Autodesk Fusion 360 part; units mm, degrees
(part 8 of 18)
  line L5414 (35.57, -188.553) -> (35.8785, -188.046)
  line L5415 (35.8585, -188.27) -> (35.5441, -188.763)
  line L5416 (63.4315, -180.974) -> (63.6222, -180.422)
  line L5417 (36.3887, -187.23) -> (36.1404, -187.759)
  line L5418 (81.0274, -184.988) -> (80.9224, -185.562)
  line L5419 (30.5713, -174.951) -> (31.1275, -175.13)
  line L5420 (25.9488, -174.854) -> (26.5208, -174.735)
  line L5421 (22.539, -190.687) -> (23.0175, -191.039)
  line L5422 (23.2676, -175.984) -> (23.7724, -175.689)
  line L5423 (32.954, -176.14) -> (32.4456, -175.833)
  line L5424 (100.022, -190.347) -> (100.453, -189.938)
  line L5425 (90.138, -191.798) -> (89.6204, -191.527)
  line L5426 (68.138, -191.798) -> (67.6204, -191.527)
  line L5427 (33.5358, -190.868) -> (33.0587, -191.205)
  line L5428 (25.6987, -192.283) -> (26.2761, -192.422)
  line L5429 (36.4559, -180.231) -> (36.6591, -180.778)
  line L5430 (102.972, -184.679) -> (103.021, -184.087)
  line L5431 (81.1268, -183.65) -> (81.1251, -183.824)
  line L5432 (28.2663, -174.602) -> (28.8498, -174.633)
  line L5433 (64.3113, -188.298) -> (64.0276, -187.787)
  line L5434 (36.6591, -180.778) -> (36.8266, -181.338)
  line L5435 (25.3856, -175.009) -> (25.9488, -174.854)
  line L5436 (90.9847, -175.246) -> (90.4345, -175.469)
  line L5437 (34.8557, -189.501) -> (35.2286, -189.039)
  line L5438 (63.9741, -187.463) -> (64.2446, -187.991)
  line L5439 (87.5489, -177.52) -> (87.157, -177.966)
  line L5440 (67.5183, -191.358) -> (68.0392, -191.643)
  line L5441 (64.1085, -179.36) -> (64.402, -178.854)
  line L5442 (63.1742, -184.617) -> (63.2578, -185.205)
  line L5443 (85.5618, -186.716) -> (85.3817, -186.16)
  line L5444 (28.0926, -192.7) -> (27.5085, -192.682)
  line L5445 (85.541, -186.358) -> (85.7392, -186.917)
  line L5446 (68.672, -192.035) -> (68.138, -191.798)
  line L5447 (28.6391, -192.587) -> (29.2302, -192.53)
  line L5448 (65.3513, -189.706) -> (64.9746, -189.259)
  line L5449 (33.9903, -190.501) -> (33.5358, -190.868)
  line L5450 (21.157, -177.966) -> (20.7955, -178.437)
  line L5451 (70.9269, -192.627) -> (70.35, -192.534)
  line L5452 (19.3443, -181.666) -> (19.232, -182.249)
  line L5453 (100.856, -189.501) -> (101.229, -189.039)
  line L5454 (22.643, -190.887) -> (22.1873, -190.521)
  line L5455 (34.0223, -190.347) -> (34.453, -189.938)
  line L5456 (93.8893, -174.697) -> (93.2963, -174.729)
  line L5457 (68.5778, -191.893) -> (69.1318, -192.107)
  line L5458 (65.6569, -189.893) -> (66.0847, -190.305)
  line L5459 (20.17, -179.446) -> (19.9088, -179.979)
  line L5460 (74.5713, -174.951) -> (75.1275, -175.13)
  line L5461 (24.672, -192.035) -> (24.138, -191.798)
  line L5462 (24.8336, -175.201) -> (25.3856, -175.009)
  line L5463 (19.7392, -186.917) -> (19.9741, -187.463)
  line L5464 (20.9746, -189.259) -> (20.6274, -188.789)
  line L5465 (65.7561, -190.127) -> (65.3513, -189.706)
  line L5466 (85.495, -181.092) -> (85.3443, -181.666)
  line L5467 (85.7774, -187.259) -> (85.5618, -186.716)
  line L5468 (35.6409, -178.681) -> (35.9457, -179.18)
  line L5469 (90.672, -192.035) -> (90.138, -191.798)
  line L5470 (101.133, -178.137) -> (100.753, -177.681)
  line L5471 (34.7525, -177.681) -> (34.3423, -177.252)
  line L5472 (19.9088, -179.979) -> (19.6834, -180.529)
  line L5473 (67.7724, -175.689) -> (68.2951, -175.428)
  line L5474 (25.7803, -192.404) -> (25.2202, -192.237)
  line L5475 (91.1318, -192.107) -> (91.6987, -192.283)
  line L5476 (36.8847, -185.267) -> (36.9725, -184.679)
  line L5477 (94.483, -174.704) -> (93.8893, -174.697)
  line L5478 (30.3945, -192.3) -> (30.9627, -192.127)
  line L5479 (20.0276, -187.787) -> (19.7774, -187.259)
  line L5480 (29.4301, -174.702) -> (30.0047, -174.808)
  line L5481 (24.5778, -191.893) -> (25.1318, -192.107)
  line L5482 (24.4345, -175.469) -> (23.9003, -175.729)
  line L5483 (34.1207, -176.914) -> (34.5428, -177.318)
  line L5484 (90.4345, -175.469) -> (89.9003, -175.729)
  line L5485 (73.2302, -192.53) -> (73.8162, -192.434)
  line L5486 (86.5495, -188.501) -> (86.8876, -188.989)
  line L5487 (63.7774, -187.259) -> (63.5618, -186.716)
  line L5488 (26.8615, -192.522) -> (27.4521, -192.583)
  line L5489 (36.1404, -187.759) -> (35.8585, -188.27)
  line L5490 (29.8162, -192.434) -> (30.3945, -192.3)
  line L5491 (37.1268, -183.65) -> (37.1251, -183.824)
  line L5492 (90.5778, -191.893) -> (91.1318, -192.107)
  line L5493 (63.1309, -185.019) -> (63.0612, -184.439)
  line L5494 (26.1233, -174.911) -> (25.5484, -175.059)
  line L5495 (20.6274, -188.789) -> (20.3113, -188.298)
  line L5496 (19.541, -186.358) -> (19.7392, -186.917)
  line L5497 (63.0332, -183.431) -> (63.0347, -183.271)
  line L5498 (65.2572, -189.454) -> (65.6569, -189.893)
  line L5499 (31.3734, -175.324) -> (30.8143, -175.124)
  line L5500 (29.075, -174.751) -> (28.483, -174.704)
  line L5501 (90.0392, -191.643) -> (90.5778, -191.893)
  line L5502 (92.9269, -192.627) -> (92.35, -192.534)
  line L5503 (85.0347, -183.271) -> (85.078, -182.688)
  line L5504 (50.8498, -174.633) -> (51.4301, -174.702)
  line L5505 (51.4301, -174.702) -> (52.0047, -174.808)
  line L5506 (52.0047, -174.808) -> (52.5713, -174.951)
  line L5507 (52.5713, -174.951) -> (53.1275, -175.13)
  line L5508 (53.1275, -175.13) -> (53.671, -175.344)
  line L5509 (53.671, -175.344) -> (54.1995, -175.594)
  line L5510 (54.1995, -175.594) -> (54.7108, -175.876)
  line L5511 (54.7108, -175.876) -> (55.2028, -176.192)
  line L5512 (55.2028, -176.192) -> (55.6734, -176.538)
  line L5513 (55.6734, -176.538) -> (56.1207, -176.914)
  line L5514 (56.1207, -176.914) -> (56.5428, -177.318)
  line L5515 (56.5428, -177.318) -> (56.9379, -177.749)
  line L5516 (56.9379, -177.749) -> (57.3045, -178.204)
  line L5517 (57.3045, -178.204) -> (57.6409, -178.681)
  line L5518 (57.6409, -178.681) -> (57.9457, -179.18)
  line L5519 (57.9457, -179.18) -> (58.2178, -179.697)
  line L5520 (58.2178, -179.697) -> (58.4559, -180.231)
  line L5521 (58.4559, -180.231) -> (58.6591, -180.778)
  line L5522 (58.6591, -180.778) -> (58.8266, -181.338)
  line L5523 (58.8266, -181.338) -> (58.9575, -181.908)
  line L5524 (58.9575, -181.908) -> (59.0514, -182.484)
  line L5525 (59.0514, -182.484) -> (59.1079, -183.066)
  line L5526 (59.1079, -183.066) -> (59.1268, -183.65)
  line L5527 (59.1268, -183.65) -> (59.1251, -183.824)
  line L5528 (59.1251, -183.824) -> (59.0951, -184.407)
  line L5529 (59.0951, -184.407) -> (59.0274, -184.988)
  line L5530 (59.0274, -184.988) -> (58.9224, -185.562)
  line L5531 (58.9224, -185.562) -> (58.7806, -186.129)
  line L5532 (58.7806, -186.129) -> (58.6024, -186.686)
  line L5533 (58.6024, -186.686) -> (58.3887, -187.23)
  line L5534 (58.3887, -187.23) -> (58.1404, -187.759)
  line L5535 (58.1404, -187.759) -> (57.8585, -188.27)
  line L5536 (57.8585, -188.27) -> (57.5441, -188.763)
  line L5537 (57.5441, -188.763) -> (57.1986, -189.234)
  line L5538 (57.1986, -189.234) -> (56.8234, -189.682)
  line L5539 (56.8234, -189.682) -> (56.42, -190.105)
  line L5540 (56.42, -190.105) -> (55.9903, -190.501)
  line L5541 (55.9903, -190.501) -> (55.5358, -190.868)
  line L5542 (55.5358, -190.868) -> (55.0587, -191.205)
  line L5543 (55.0587, -191.205) -> (54.5607, -191.511)
  line L5544 (54.5607, -191.511) -> (54.0441, -191.784)
  line L5545 (54.0441, -191.784) -> (53.5109, -192.023)
  line L5546 (53.5109, -192.023) -> (52.9634, -192.227)
  line L5547 (52.9634, -192.227) -> (52.4039, -192.396)
  line L5548 (52.4039, -192.396) -> (51.8346, -192.528)
  line L5549 (51.8346, -192.528) -> (51.2581, -192.623)
  line L5550 (51.2581, -192.623) -> (50.6766, -192.68)
  line L5551 (50.6766, -192.68) -> (50.0926, -192.7)
  line L5552 (50.0926, -192.7) -> (49.5085, -192.682)
  line L5553 (49.5085, -192.682) -> (48.9269, -192.627)
  line L5554 (48.9269, -192.627) -> (48.35, -192.534)
  line L5555 (48.35, -192.534) -> (47.7803, -192.404)
  line L5556 (47.7803, -192.404) -> (47.2202, -192.237)
  line L5557 (47.2202, -192.237) -> (46.672, -192.035)
  line L5558 (46.672, -192.035) -> (46.138, -191.798)
  line L5559 (46.138, -191.798) -> (45.6204, -191.527)
  line L5560 (45.6204, -191.527) -> (45.1214, -191.223)
  line L5561 (45.1214, -191.223) -> (44.643, -190.887)
  line L5562 (44.643, -190.887) -> (44.1873, -190.521)
  line L5563 (44.1873, -190.521) -> (43.7561, -190.127)
  line L5564 (43.7561, -190.127) -> (43.3513, -189.706)
  line L5565 (43.3513, -189.706) -> (42.9746, -189.259)
  line L5566 (42.9746, -189.259) -> (42.6274, -188.789)
  line L5567 (42.6274, -188.789) -> (42.3113, -188.298)
  line L5568 (42.3113, -188.298) -> (42.0276, -187.787)
  line L5569 (42.0276, -187.787) -> (41.7774, -187.259)
  line L5570 (41.7774, -187.259) -> (41.5618, -186.716)
  line L5571 (41.5618, -186.716) -> (41.3817, -186.16)
  line L5572 (41.3817, -186.16) -> (41.2379, -185.593)
  line L5573 (41.2379, -185.593) -> (41.1309, -185.019)
  line L5574 (41.1309, -185.019) -> (41.0612, -184.439)
  line L5575 (41.0612, -184.439) -> (41.0291, -183.855)
  line L5576 (41.0291, -183.855) -> (41.0332, -183.431)
  line L5577 (41.0332, -183.431) -> (41.0347, -183.271)
  line L5578 (41.0347, -183.271) -> (41.078, -182.688)
  line L5579 (41.1742, -184.617) -> (41.2578, -185.205)
  line L5580 (41.2578, -185.205) -> (41.3803, -185.786)
  line L5581 (41.3803, -185.786) -> (41.541, -186.358)
  line L5582 (41.541, -186.358) -> (41.7392, -186.917)
  line L5583 (41.7392, -186.917) -> (41.9741, -187.463)
  line L5584 (41.9741, -187.463) -> (42.2446, -187.991)
  line L5585 (42.2446, -187.991) -> (42.5495, -188.501)
  line L5586 (42.5495, -188.501) -> (42.8876, -188.989)
  line L5587 (42.8876, -188.989) -> (43.2572, -189.454)
  line L5588 (43.2572, -189.454) -> (43.6569, -189.893)
  line L5589 (43.6569, -189.893) -> (44.0847, -190.305)
  line L5590 (44.0847, -190.305) -> (44.539, -190.687)
  line L5591 (44.539, -190.687) -> (45.0175, -191.039)
  line L5592 (45.0175, -191.039) -> (45.5183, -191.358)
  line L5593 (45.5183, -191.358) -> (46.0392, -191.643)
  line L5594 (46.0392, -191.643) -> (46.5778, -191.893)
  line L5595 (46.5778, -191.893) -> (47.1318, -192.107)
  line L5596 (47.1318, -192.107) -> (47.6987, -192.283)
  line L5597 (47.6987, -192.283) -> (48.2761, -192.422)
  line L5598 (48.2761, -192.422) -> (48.8615, -192.522)
  line L5599 (48.8615, -192.522) -> (49.4521, -192.583)
  line L5600 (49.4521, -192.583) -> (50.0455, -192.605)
  line L5601 (50.0455, -192.605) -> (50.6391, -192.587)
  line L5602 (50.6391, -192.587) -> (51.2302, -192.53)
  line L5603 (51.2302, -192.53) -> (51.8162, -192.434)
  line L5604 (51.8162, -192.434) -> (52.3945, -192.3)
  line L5605 (52.3945, -192.3) -> (52.9627, -192.127)
  line L5606 (52.9627, -192.127) -> (53.5182, -191.917)
  line L5607 (53.5182, -191.917) -> (54.0585, -191.671)
  line L5608 (54.0585, -191.671) -> (54.5813, -191.39)
  line L5609 (54.5813, -191.39) -> (55.0844, -191.074)
  line L5610 (55.0844, -191.074) -> (55.5654, -190.726)
  line L5611 (55.5654, -190.726) -> (56.0223, -190.347)
  line L5612 (56.0223, -190.347) -> (56.453, -189.938)
  line L5613 (56.453, -189.938) -> (56.8557, -189.501)
  line L5614 (56.8557, -189.501) -> (57.2286, -189.039)
  line L5615 (57.2286, -189.039) -> (57.57, -188.553)
  line L5616 (57.57, -188.553) -> (57.8785, -188.046)
  line L5617 (57.8785, -188.046) -> (58.1527, -187.519)
  line L5618 (58.1527, -187.519) -> (58.3914, -186.976)
  line L5619 (58.3914, -186.976) -> (58.5935, -186.417)
  line L5620 (58.5935, -186.417) -> (58.7582, -185.847)
  line L5621 (58.7582, -185.847) -> (58.8847, -185.267)
  line L5622 (58.8847, -185.267) -> (58.9725, -184.679)
  line L5623 (58.9725, -184.679) -> (59.0211, -184.087)
  line L5624 (59.0211, -184.087) -> (59.0318, -183.65)
  line L5625 (59.0318, -183.65) -> (59.0121, -183.057)
  line L5626 (59.0121, -183.057) -> (58.9531, -182.466)
  line L5627 (58.9531, -182.466) -> (58.8551, -181.88)
  line L5628 (58.8551, -181.88) -> (58.7185, -181.302)
  line L5629 (58.7185, -181.302) -> (58.5439, -180.735)
  line L5630 (58.5439, -180.735) -> (58.3321, -180.18)
  line L5631 (58.3321, -180.18) -> (58.084, -179.64)
  line L5632 (58.084, -179.64) -> (57.8006, -179.118)
  line L5633 (57.8006, -179.118) -> (57.4833, -178.617)
  line L5634 (57.4833, -178.617) -> (57.1334, -178.137)
  line L5635 (57.1334, -178.137) -> (56.7525, -177.681)
  line L5636 (56.7525, -177.681) -> (56.3423, -177.252)
  line L5637 (56.3423, -177.252) -> (55.9045, -176.851)
  line L5638 (55.9045, -176.851) -> (55.4411, -176.479)
  line L5639 (55.4411, -176.479) -> (54.954, -176.14)
  line L5640 (54.954, -176.14) -> (54.4456, -175.833)
  line L5641 (54.4456, -175.833) -> (53.9179, -175.561)
  line L5642 (53.9179, -175.561) -> (53.3734, -175.324)
  line L5643 (53.3734, -175.324) -> (52.8143, -175.124)
  line L5644 (52.8143, -175.124) -> (52.2432, -174.961)
  line L5645 (52.2432, -174.961) -> (51.6626, -174.837)
  line L5646 (51.6626, -174.837) -> (51.075, -174.751)
  line L5647 (51.075, -174.751) -> (50.483, -174.704)
  line L5648 (50.483, -174.704) -> (49.8893, -174.697)
  line L5649 (49.8893, -174.697) -> (49.2963, -174.729)
  line L5650 (49.2963, -174.729) -> (48.7068, -174.8)
  line L5651 (48.7068, -174.8) -> (48.1233, -174.911)
  line L5652 (48.1233, -174.911) -> (47.5484, -175.059)
  line L5653 (47.5484, -175.059) -> (46.9847, -175.246)
  line L5654 (46.9847, -175.246) -> (46.4345, -175.469)
  line L5655 (46.4345, -175.469) -> (45.9003, -175.729)
  line L5656 (45.9003, -175.729) -> (45.3845, -176.023)
  line L5657 (45.3845, -176.023) -> (44.8893, -176.351)
  line L5658 (44.8893, -176.351) -> (44.417, -176.71)
  line L5659 (44.417, -176.71) -> (43.9695, -177.101)
  line L5660 (43.9695, -177.101) -> (43.5489, -177.52)
  line L5661 (43.5489, -177.52) -> (43.157, -177.966)
  line L5662 (43.157, -177.966) -> (42.7955, -178.437)
  line L5663 (42.7955, -178.437) -> (42.466, -178.931)
  line L5664 (42.466, -178.931) -> (42.17, -179.446)
  line L5665 (42.17, -179.446) -> (41.9088, -179.979)
  line L5666 (41.9088, -179.979) -> (41.6834, -180.529)
  line L5667 (41.6834, -180.529) -> (41.495, -181.092)
  line L5668 (41.495, -181.092) -> (41.3443, -181.666)
  line L5669 (41.3443, -181.666) -> (41.2321, -182.249)
  line L5670 (41.2321, -182.249) -> (41.1587, -182.838)
  line L5671 (41.1587, -182.838) -> (41.1245, -183.431)
  line L5672 (41.1245, -183.431) -> (41.1297, -184.025)
  line L5673 (41.1297, -184.025) -> (41.1742, -184.617)
  line L5674 (129.078, -158.988) -> (129.159, -158.41)
  line L5675 (129.159, -158.41) -> (129.277, -157.837)
  line L5676 (129.277, -157.837) -> (129.432, -157.274)
  line L5677 (129.432, -157.274) -> (129.622, -156.722)
  line L5678 (129.622, -156.722) -> (129.848, -156.183)
  line L5679 (129.848, -156.183) -> (130.108, -155.66)
  line L5680 (130.108, -155.66) -> (130.402, -155.154)
  line L5681 (130.402, -155.154) -> (130.727, -154.669)
  line L5682 (130.727, -154.669) -> (131.084, -154.206)
  line L5683 (131.084, -154.206) -> (131.469, -153.766)
  line L5684 (131.469, -153.766) -> (131.882, -153.353)
  line L5685 (131.882, -153.353) -> (132.32, -152.967)
  line L5686 (132.32, -152.967) -> (132.783, -152.61)
  line L5687 (132.783, -152.61) -> (133.268, -152.284)
  line L5688 (133.268, -152.284) -> (133.772, -151.989)
  line L5689 (133.772, -151.989) -> (134.295, -151.728)
  line L5690 (134.295, -151.728) -> (134.834, -151.501)
  line L5691 (134.834, -151.501) -> (135.386, -151.309)
  line L5692 (135.386, -151.309) -> (135.949, -151.154)
  line L5693 (135.949, -151.154) -> (136.521, -151.035)
  line L5694 (136.521, -151.035) -> (137.099, -150.953)
  line L5695 (137.099, -150.953) -> (137.682, -150.909)
  line L5696 (137.682, -150.909) -> (138.266, -150.902)
  line L5697 (138.266, -150.902) -> (138.85, -150.933)
  line L5698 (138.85, -150.933) -> (139.43, -151.002)
  line L5699 (139.43, -151.002) -> (140.005, -151.108)
  line L5700 (140.005, -151.108) -> (140.571, -151.251)
  line L5701 (140.571, -151.251) -> (141.128, -151.43)
  line L5702 (141.128, -151.43) -> (141.671, -151.644)
  line L5703 (141.671, -151.644) -> (142.199, -151.894)
  line L5704 (142.199, -151.894) -> (142.711, -152.176)
  line L5705 (142.711, -152.176) -> (143.203, -152.492)
  line L5706 (143.203, -152.492) -> (143.673, -152.838)
  line L5707 (143.673, -152.838) -> (144.121, -153.214)
  line L5708 (144.121, -153.214) -> (144.543, -153.618)
  line L5709 (144.543, -153.618) -> (144.938, -154.049)
  line L5710 (144.938, -154.049) -> (145.304, -154.504)
  line L5711 (145.304, -154.504) -> (145.641, -154.981)
  line L5712 (145.641, -154.981) -> (145.946, -155.48)
  line L5713 (145.946, -155.48) -> (146.218, -155.997)
  line L5714 (146.218, -155.997) -> (146.456, -156.531)
  line L5715 (146.456, -156.531) -> (146.659, -157.078)
  line L5716 (146.659, -157.078) -> (146.827, -157.638)
  line L5717 (146.827, -157.638) -> (146.957, -158.208)
  line L5718 (146.957, -158.208) -> (147.051, -158.784)
  line L5719 (147.051, -158.784) -> (147.108, -159.366)
  line L5720 (147.108, -159.366) -> (147.127, -159.95)
  line L5721 (147.127, -159.95) -> (147.125, -160.124)
  line L5722 (147.125, -160.124) -> (147.095, -160.707)
  line L5723 (147.095, -160.707) -> (147.027, -161.288)
  line L5724 (147.027, -161.288) -> (146.922, -161.862)
  line L5725 (146.922, -161.862) -> (146.781, -162.429)
  line L5726 (146.781, -162.429) -> (146.602, -162.986)
  line L5727 (146.602, -162.986) -> (146.389, -163.53)
  line L5728 (146.389, -163.53) -> (146.14, -164.059)
  line L5729 (146.14, -164.059) -> (145.858, -164.57)
  line L5730 (145.858, -164.57) -> (145.544, -165.063)
  line L5731 (145.544, -165.063) -> (145.199, -165.534)
  line L5732 (145.199, -165.534) -> (144.823, -165.982)
  line L5733 (144.823, -165.982) -> (144.42, -166.405)
  line L5734 (144.42, -166.405) -> (143.99, -166.801)
  line L5735 (143.99, -166.801) -> (143.536, -167.168)
  line L5736 (143.536, -167.168) -> (143.059, -167.505)
  line L5737 (143.059, -167.505) -> (142.561, -167.811)
  line L5738 (142.561, -167.811) -> (142.044, -168.084)
  line L5739 (142.044, -168.084) -> (141.511, -168.323)
  line L5740 (141.511, -168.323) -> (140.963, -168.527)
  line L5741 (140.963, -168.527) -> (140.404, -168.696)
  line L5742 (140.404, -168.696) -> (139.835, -168.828)
  line L5743 (139.835, -168.828) -> (139.258, -168.923)
  line L5744 (139.258, -168.923) -> (138.677, -168.98)
  line L5745 (138.677, -168.98) -> (138.093, -169)
  line L5746 (138.093, -169) -> (137.509, -168.982)
  line L5747 (137.509, -168.982) -> (136.927, -168.927)
  line L5748 (136.927, -168.927) -> (136.35, -168.834)
  line L5749 (136.35, -168.834) -> (135.78, -168.704)
  line L5750 (135.78, -168.704) -> (135.22, -168.537)
  line L5751 (135.22, -168.537) -> (134.672, -168.335)
  line L5752 (134.672, -168.335) -> (134.138, -168.098)
  line L5753 (134.138, -168.098) -> (133.62, -167.827)
  line L5754 (133.62, -167.827) -> (133.121, -167.523)
  line L5755 (133.121, -167.523) -> (132.643, -167.187)
  line L5756 (132.643, -167.187) -> (132.187, -166.821)
  line L5757 (132.187, -166.821) -> (131.756, -166.427)
  line L5758 (131.756, -166.427) -> (131.351, -166.006)
  line L5759 (131.351, -166.006) -> (130.975, -165.559)
  line L5760 (130.975, -165.559) -> (130.627, -165.089)
  line L5761 (130.627, -165.089) -> (130.311, -164.598)
  line L5762 (130.311, -164.598) -> (130.028, -164.087)
  line L5763 (130.028, -164.087) -> (129.777, -163.559)
  line L5764 (129.777, -163.559) -> (129.562, -163.016)
  line L5765 (129.562, -163.016) -> (129.382, -162.46)
  line L5766 (129.382, -162.46) -> (129.238, -161.893)
  line L5767 (129.238, -161.893) -> (129.131, -161.319)
  line L5768 (129.131, -161.319) -> (129.061, -160.739)
  line L5769 (129.061, -160.739) -> (129.029, -160.155)
  line L5770 (129.029, -160.155) -> (129.033, -159.731)
  line L5771 (129.033, -159.731) -> (129.035, -159.571)
  line L5772 (129.035, -159.571) -> (129.078, -158.988)
  line L5773 (129.174, -160.917) -> (129.258, -161.505)
  line L5774 (129.258, -161.505) -> (129.38, -162.086)
  line L5775 (129.38, -162.086) -> (129.541, -162.658)
  line L5776 (129.541, -162.658) -> (129.739, -163.217)
  line L5777 (129.739, -163.217) -> (129.974, -163.763)
  line L5778 (129.974, -163.763) -> (130.245, -164.291)
  line L5779 (130.245, -164.291) -> (130.55, -164.801)
  line L5780 (130.55, -164.801) -> (130.888, -165.289)
  line L5781 (130.888, -165.289) -> (131.257, -165.754)
  line L5782 (131.257, -165.754) -> (131.657, -166.193)
  line L5783 (122.823, -94.8821) -> (122.42, -95.3049)
  line L5784 (122.42, -95.3049) -> (121.99, -95.7008)
  line L5785 (121.99, -95.7008) -> (121.536, -96.0681)
  line L5786 (121.536, -96.0681) -> (121.059, -96.4054)
  line L5787 (121.059, -96.4054) -> (120.561, -96.7111)
  line L5788 (120.561, -96.7111) -> (120.044, -96.9841)
  line L5789 (120.044, -96.9841) -> (119.511, -97.2231)
  line L5790 (119.511, -97.2231) -> (118.963, -97.4273)
  line L5791 (118.963, -97.4273) -> (118.404, -97.5957)
  line L5792 (118.404, -97.5957) -> (117.835, -97.7276)
  line L5793 (117.835, -97.7276) -> (117.258, -97.8226)
  line L5794 (117.258, -97.8226) -> (116.677, -97.8801)
  line L5795 (116.677, -97.8801) -> (116.093, -97.9)
  line L5796 (116.093, -97.9) -> (115.509, -97.8821)
  line L5797 (115.509, -97.8821) -> (114.927, -97.8266)
  line L5798 (114.927, -97.8266) -> (114.35, -97.7337)
  line L5799 (114.35, -97.7337) -> (113.78, -97.6038)
  line L5800 (113.78, -97.6038) -> (113.22, -97.4373)
  line L5801 (113.22, -97.4373) -> (112.672, -97.2351)
  line L5802 (112.672, -97.2351) -> (112.138, -96.9979)
  line L5803 (112.138, -96.9979) -> (111.62, -96.7267)
  line L5804 (111.62, -96.7267) -> (111.121, -96.4227)
  line L5805 (111.121, -96.4227) -> (110.643, -96.0871)
  line L5806 (110.643, -96.0871) -> (110.187, -95.7214)
  line L5807 (110.187, -95.7214) -> (109.756, -95.327)
  line L5808 (109.756, -95.327) -> (109.351, -94.9056)
  line L5809 (109.351, -94.9056) -> (108.975, -94.459)
  line L5810 (108.975, -94.459) -> (108.627, -93.989)
  line L5811 (108.627, -93.989) -> (108.311, -93.4975)
  line L5812 (108.311, -93.4975) -> (108.028, -92.9867)
  line L5813 (108.028, -92.9867) -> (107.777, -92.4587)
  line L5814 (107.777, -92.4587) -> (107.562, -91.9156)
  line L5815 (107.562, -91.9156) -> (107.382, -91.3597)
  line L5816 (107.382, -91.3597) -> (107.238, -90.7934)
  line L5817 (107.238, -90.7934) -> (107.131, -90.2189)
  line L5818 (107.131, -90.2189) -> (107.061, -89.6388)
  line L5819 (107.061, -89.6388) -> (107.029, -89.0553)
  line L5820 (107.029, -89.0553) -> (107.033, -88.6312)
  line L5821 (107.033, -88.6312) -> (107.035, -88.471)
  line L5822 (107.035, -88.471) -> (107.078, -87.8883)
  line L5823 (107.174, -89.8171) -> (107.258, -90.405)
  line L5824 (107.258, -90.405) -> (107.38, -90.9861)
  line L5825 (107.38, -90.9861) -> (107.541, -91.5577)
  line L5826 (107.541, -91.5577) -> (107.739, -92.1175)
  line L5827 (107.739, -92.1175) -> (107.974, -92.6629)
  line L5828 (107.974, -92.6629) -> (108.245, -93.1915)
  line L5829 (108.245, -93.1915) -> (108.55, -93.701)
  line L5830 (108.55, -93.701) -> (108.888, -94.1892)
  line L5831 (108.888, -94.1892) -> (109.257, -94.6539)
  line L5832 (109.257, -94.6539) -> (109.657, -95.0931)
  line L5833 (109.657, -95.0931) -> (110.085, -95.5049)
  line L5834 (110.085, -95.5049) -> (110.539, -95.8873)
  line L5835 (110.539, -95.8873) -> (111.018, -96.2389)
  line L5836 (111.018, -96.2389) -> (111.518, -96.5579)
  line L5837 (111.518, -96.5579) -> (112.039, -96.8431)
  line L5838 (112.039, -96.8431) -> (112.578, -97.0931)
  line L5839 (112.578, -97.0931) -> (113.132, -97.3069)
  line L5840 (113.132, -97.3069) -> (113.699, -97.4835)
  line L5841 (113.699, -97.4835) -> (114.276, -97.6221)
  line L5842 (114.276, -97.6221) -> (114.861, -97.7221)
  line L5843 (114.861, -97.7221) -> (115.452, -97.7832)
  line L5844 (115.452, -97.7832) -> (116.046, -97.8049)
  line L5845 (116.046, -97.8049) -> (116.639, -97.7873)
  line L5846 (116.639, -97.7873) -> (117.23, -97.7304)
  line L5847 (117.23, -97.7304) -> (117.816, -97.6345)
  line L5848 (117.816, -97.6345) -> (118.395, -97.4999)
  line L5849 (118.395, -97.4999) -> (118.963, -97.3272)
  line L5850 (118.963, -97.3272) -> (119.518, -97.1173)
  line L5851 (119.518, -97.1173) -> (120.059, -96.8711)
  line L5852 (120.059, -96.8711) -> (120.581, -96.5896)
  line L5853 (120.581, -96.5896) -> (121.084, -96.274)
  line L5854 (121.084, -96.274) -> (121.565, -95.9258)
  line L5855 (121.565, -95.9258) -> (122.022, -95.5465)
  line L5856 (122.022, -95.5465) -> (122.453, -95.1378)
  line L5857 (122.453, -95.1378) -> (122.856, -94.7014)
  line L5858 (122.856, -94.7014) -> (123.229, -94.2393)
  line L5859 (123.229, -94.2393) -> (123.57, -93.7534)
  line L5860 (123.57, -93.7534) -> (123.879, -93.246)
  line L5861 (123.879, -93.246) -> (124.153, -92.7193)
  line L5862 (124.153, -92.7193) -> (124.391, -92.1756)
  line L5863 (124.391, -92.1756) -> (124.594, -91.6172)
  line L5864 (124.594, -91.6172) -> (124.758, -91.0467)
  line L5865 (124.758, -91.0467) -> (124.885, -90.4665)
  line L5866 (124.885, -90.4665) -> (124.972, -89.8793)
  line L5867 (124.972, -89.8793) -> (125.021, -89.2874)
  line L5868 (125.021, -89.2874) -> (125.032, -88.85)
  line L5869 (125.032, -88.85) -> (125.012, -88.2565)
  line L5870 (125.012, -88.2565) -> (124.953, -87.6656)
  line L5871 (124.953, -87.6656) -> (124.855, -87.08)
  line L5872 (124.855, -87.08) -> (124.719, -86.5021)
  line L5873 (124.719, -86.5021) -> (124.544, -85.9345)
  line L5874 (124.544, -85.9345) -> (124.332, -85.3798)
  line L5875 (124.332, -85.3798) -> (124.084, -84.8403)
  line L5876 (124.084, -84.8403) -> (123.801, -84.3185)
  line L5877 (123.801, -84.3185) -> (123.483, -83.8165)
  line L5878 (123.483, -83.8165) -> (123.133, -83.3368)
  line L5879 (123.133, -83.3368) -> (122.753, -82.8812)
  line L5880 (122.753, -82.8812) -> (122.342, -82.4519)
  line L5881 (122.342, -82.4519) -> (121.904, -82.0507)
  line L5882 (121.904, -82.0507) -> (121.441, -81.6795)
  line L5883 (121.441, -81.6795) -> (120.954, -81.3397)
  line L5884 (120.954, -81.3397) -> (120.446, -81.033)
  line L5885 (120.446, -81.033) -> (119.918, -80.7606)
  line L5886 (119.918, -80.7606) -> (119.373, -80.5239)
  line L5887 (119.373, -80.5239) -> (118.814, -80.3237)
  line L5888 (118.814, -80.3237) -> (118.243, -80.161)
  line L5889 (118.243, -80.161) -> (117.663, -80.0365)
  line L5890 (117.663, -80.0365) -> (117.075, -79.9508)
  line L5891 (117.075, -79.9508) -> (116.483, -79.9042)
  line L5892 (116.483, -79.9042) -> (115.889, -79.897)
  line L5893 (115.889, -79.897) -> (115.296, -79.9291)
  line L5894 (115.296, -79.9291) -> (114.707, -80.0004)
  line L5895 (114.707, -80.0004) -> (114.123, -80.1107)
  line L5896 (114.123, -80.1107) -> (113.548, -80.2593)
  line L5897 (113.548, -80.2593) -> (112.985, -80.4458)
  line L5898 (112.985, -80.4458) -> (112.434, -80.6692)
  line L5899 (112.434, -80.6692) -> (111.9, -80.9286)
  line L5900 (111.9, -80.9286) -> (111.385, -81.2228)
  line L5901 (111.385, -81.2228) -> (110.889, -81.5505)
  line L5902 (110.889, -81.5505) -> (110.417, -81.9104)
  line L5903 (110.417, -81.9104) -> (109.97, -82.3007)
  line L5904 (109.97, -82.3007) -> (109.549, -82.7199)
  line L5905 (109.549, -82.7199) -> (109.157, -83.166)
  line L5906 (109.157, -83.166) -> (108.795, -83.6371)
  line L5907 (108.795, -83.6371) -> (108.466, -84.1311)
  line L5908 (108.466, -84.1311) -> (108.17, -84.6459)
  line L5909 (108.17, -84.6459) -> (107.909, -85.1791)
  line L5910 (107.909, -85.1791) -> (107.683, -85.7285)
  line L5911 (107.683, -85.7285) -> (107.495, -86.2917)
  line L5912 (107.495, -86.2917) -> (107.344, -86.866)
  line L5913 (107.344, -86.866) -> (107.232, -87.4491)
  line L5914 (107.232, -87.4491) -> (107.159, -88.0384)
  line L5915 (107.159, -88.0384) -> (107.124, -88.6312)
  line L5916 (107.124, -88.6312) -> (107.13, -89.225)
  line L5917 (107.13, -89.225) -> (107.174, -89.8171)
  line L5918 (151.078, -87.8883) -> (151.159, -87.3096)
  line L5919 (151.159, -87.3096) -> (151.277, -86.7373)
  line L5920 (151.277, -86.7373) -> (151.432, -86.1738)
  line L5921 (151.432, -86.1738) -> (151.622, -85.6215)
  line L5922 (151.622, -85.6215) -> (151.848, -85.0827)
  line L5923 (151.848, -85.0827) -> (152.108, -84.5595)
  line L5924 (152.108, -84.5595) -> (152.402, -84.0542)
  line L5925 (152.402, -84.0542) -> (152.727, -83.569)
  line L5926 (152.727, -83.569) -> (153.084, -83.1057)
  line L5927 (153.084, -83.1057) -> (153.469, -82.6664)
  line L5928 (153.469, -82.6664) -> (153.882, -82.2528)
  line L5929 (153.882, -82.2528) -> (154.32, -81.8668)
  line L5930 (154.32, -81.8668) -> (154.783, -81.5099)
  line L5931 (154.783, -81.5099) -> (155.268, -81.1835)
  line L5932 (155.268, -81.1835) -> (155.772, -80.8892)
  line L5933 (155.772, -80.8892) -> (156.295, -80.628)
  line L5934 (156.295, -80.628) -> (156.834, -80.4011)
  line L5935 (156.834, -80.4011) -> (157.386, -80.2094)
  line L5936 (157.386, -80.2094) -> (157.949, -80.0538)
  line L5937 (157.949, -80.0538) -> (158.521, -79.9348)
  line L5938 (158.521, -79.9348) -> (159.099, -79.8529)
  line L5939 (159.099, -79.8529) -> (159.682, -79.8086)
  line L5940 (159.682, -79.8086) -> (160.266, -79.802)
  line L5941 (160.266, -79.802) -> (160.85, -79.8331)
  line L5942 (160.85, -79.8331) -> (161.43, -79.9018)
  line L5943 (161.43, -79.9018) -> (162.005, -80.0077)
  line L5944 (162.005, -80.0077) -> (162.571, -80.1506)
  line L5945 (162.571, -80.1506) -> (163.128, -80.3297)
  line L5946 (163.128, -80.3297) -> (163.671, -80.5443)
  line L5947 (163.671, -80.5443) -> (164.199, -80.7936)
  line L5948 (164.199, -80.7936) -> (164.711, -81.0764)
  line L5949 (164.711, -81.0764) -> (165.203, -81.3917)
  line L5950 (165.203, -81.3917) -> (165.673, -81.738)
  line L5951 (165.673, -81.738) -> (166.121, -82.114)
  line L5952 (166.121, -82.114) -> (166.543, -82.518)
  line L5953 (166.543, -82.518) -> (166.938, -82.9485)
  line L5954 (166.938, -82.9485) -> (167.304, -83.4036)
  line L5955 (167.304, -83.4036) -> (167.641, -83.8813)
  line L5956 (167.641, -83.8813) -> (167.946, -84.3798)
  line L5957 (167.946, -84.3798) -> (168.218, -84.8969)
  line L5958 (168.218, -84.8969) -> (168.456, -85.4305)
  line L5959 (168.456, -85.4305) -> (168.659, -85.9784)
  line L5960 (168.659, -85.9784) -> (168.827, -86.5382)
  line L5961 (168.827, -86.5382) -> (168.957, -87.1077)
  line L5962 (168.957, -87.1077) -> (169.051, -87.6844)
  line L5963 (169.051, -87.6844) -> (169.108, -88.266)
  line L5964 (169.108, -88.266) -> (169.127, -88.85)
  line L5965 (169.127, -88.85) -> (169.125, -89.0237)
  line L5966 (169.125, -89.0237) -> (169.095, -89.6073)
  line L5967 (169.095, -89.6073) -> (169.027, -90.1877)
  line L5968 (169.027, -90.1877) -> (168.922, -90.7625)
  line L5969 (168.922, -90.7625) -> (168.781, -91.3293)
  line L5970 (168.781, -91.3293) -> (168.602, -91.8858)
  line L5971 (168.602, -91.8858) -> (168.389, -92.4297)
  line L5972 (168.389, -92.4297) -> (168.14, -92.9586)
  line L5973 (168.14, -92.9586) -> (167.858, -93.4704)
  line L5974 (167.858, -93.4704) -> (167.544, -93.963)
  line L5975 (167.544, -93.963) -> (167.199, -94.4342)
  line L5976 (167.199, -94.4342) -> (166.823, -94.8821)
  line L5977 (166.823, -94.8821) -> (166.42, -95.3049)
  line L5978 (166.42, -95.3049) -> (165.99, -95.7008)
  line L5979 (165.99, -95.7008) -> (165.536, -96.0681)
  line L5980 (165.536, -96.0681) -> (165.059, -96.4054)
  line L5981 (165.059, -96.4054) -> (164.561, -96.7111)
  line L5982 (164.561, -96.7111) -> (164.044, -96.9841)
  line L5983 (164.044, -96.9841) -> (163.511, -97.2231)
  line L5984 (163.511, -97.2231) -> (162.963, -97.4273)
  line L5985 (162.963, -97.4273) -> (162.404, -97.5957)
  line L5986 (162.404, -97.5957) -> (161.835, -97.7276)
  line L5987 (161.835, -97.7276) -> (161.258, -97.8226)
  line L5988 (161.258, -97.8226) -> (160.677, -97.8801)
  line L5989 (160.677, -97.8801) -> (160.093, -97.9)
  line L5990 (160.093, -97.9) -> (159.509, -97.8821)
  line L5991 (159.509, -97.8821) -> (158.927, -97.8266)
  line L5992 (158.927, -97.8266) -> (158.35, -97.7337)
  line L5993 (158.35, -97.7337) -> (157.78, -97.6038)
  line L5994 (157.78, -97.6038) -> (157.22, -97.4373)
  line L5995 (157.22, -97.4373) -> (156.672, -97.2351)
  line L5996 (156.672, -97.2351) -> (156.138, -96.9979)
  line L5997 (156.138, -96.9979) -> (155.62, -96.7267)
  line L5998 (155.62, -96.7267) -> (155.121, -96.4227)
  line L5999 (155.121, -96.4227) -> (154.643, -96.0871)
  line L6000 (154.643, -96.0871) -> (154.187, -95.7214)
  line L6001 (154.187, -95.7214) -> (153.756, -95.327)
  line L6002 (153.756, -95.327) -> (153.351, -94.9056)
  line L6003 (153.351, -94.9056) -> (152.975, -94.459)
  line L6004 (152.975, -94.459) -> (152.627, -93.989)
  line L6005 (152.627, -93.989) -> (152.311, -93.4975)
  line L6006 (152.311, -93.4975) -> (152.028, -92.9867)
  line L6007 (152.028, -92.9867) -> (151.777, -92.4587)
  line L6008 (151.777, -92.4587) -> (151.562, -91.9156)
  line L6009 (151.562, -91.9156) -> (151.382, -91.3597)
  line L6010 (151.382, -91.3597) -> (151.238, -90.7934)
  line L6011 (151.238, -90.7934) -> (151.131, -90.2189)
  line L6012 (151.131, -90.2189) -> (151.061, -89.6388)
  line L6013 (151.061, -89.6388) -> (151.029, -89.0553)
  line L6014 (151.029, -89.0553) -> (151.033, -88.6312)
  line L6015 (151.033, -88.6312) -> (151.035, -88.471)
  line L6016 (146.14, -45.5586) -> (145.858, -46.0704)
  line L6017 (32.5813, -167.69) -> (33.0844, -167.374)
  line L6018 (142.581, -49.1896) -> (143.084, -48.874)
  line L6019 (37.0318, -159.95) -> (37.0121, -159.357)
  line L6020 (23.9003, -152.029) -> (23.3845, -152.323)
  line L6021 (144.856, -47.3014) -> (145.229, -46.8393)
  line L6022 (21.7561, -166.427) -> (21.3513, -166.006)
  line L6023 (28.0926, -169) -> (27.5085, -168.982)
  line L6024 (42.466, -60.4311) -> (42.17, -60.9459)
  line L6025 (20.5495, -164.801) -> (20.8876, -165.289)
  line L6026 (136.521, -32.5348) -> (137.099, -32.4529)
  line L6027 (141.918, -151.861) -> (141.373, -151.624)
  line L6028 (132.889, -152.651) -> (132.417, -153.01)
  line L6029 (24.0392, -167.943) -> (24.5778, -168.193)
  line L6030 (21.5489, -153.82) -> (21.157, -154.266)
  line L6031 (33.6734, -152.838) -> (34.1207, -153.214)
  line L6032 (37.0121, -159.357) -> (36.9531, -158.766)
  line L6033 (139.075, -151.051) -> (138.483, -151.004)
  line L6034 (31.5182, -168.217) -> (32.0585, -167.971)
  line L6035 (42.402, -155.154) -> (42.7274, -154.669)
  line L6036 (28.2663, -150.902) -> (28.8498, -150.933)
  line L6037 (138.677, -50.4801) -> (138.093, -50.5)
  line L6038 (22.1873, -166.821) -> (21.7561, -166.427)
  line L6039 (142.581, -167.69) -> (143.084, -167.374)
  line L6040 (19.3817, -162.46) -> (19.2379, -161.893)
  line L6041 (146.953, -158.766) -> (146.855, -158.18)
  line L6042 (36.6591, -157.078) -> (36.8266, -157.638)
  line L6043 (22.3203, -152.967) -> (22.7829, -152.61)
  line L6044 (138.093, -50.5) -> (137.509, -50.4821)
  line L6045 (41.3443, -63.166) -> (41.2321, -63.7491)
  line L6046 (140.005, -32.6077) -> (140.571, -32.7506)
  line L6047 (20.17, -155.746) -> (19.9088, -156.279)
  line L6048 (131.549, -153.82) -> (131.157, -154.266)
  line L6049 (147.032, -159.95) -> (147.012, -159.357)
  line L6050 (19.078, -158.988) -> (19.1589, -158.41)
  line L6051 (22.8893, -152.651) -> (22.417, -153.01)
  line L6052 (146.972, -42.4793) -> (147.021, -41.8875)
  line L6053 (19.9088, -156.279) -> (19.6834, -156.829)
  line L6054 (130.028, -45.5867) -> (129.777, -45.0587)
  line L6055 (23.2676, -152.284) -> (23.7724, -151.989)
  line L6056 (129.232, -158.549) -> (129.159, -159.138)
  line L6057 (138.266, -32.402) -> (138.85, -32.4331)
  line L6058 (146.855, -158.18) -> (146.719, -157.602)
  line L6059 (29.2302, -168.83) -> (29.8162, -168.734)
  line L6060 (129.495, -157.392) -> (129.344, -157.966)
  line L6061 (139.43, -32.5018) -> (140.005, -32.6077)
  line L6062 (29.2581, -168.923) -> (28.6766, -168.98)
  line L6063 (135.548, -151.359) -> (134.985, -151.546)
  line L6064 (147.125, -41.6237) -> (147.095, -42.2073)
  line L6065 (33.0844, -167.374) -> (33.5654, -167.026)
  line L6066 (138.639, -50.3873) -> (139.23, -50.3304)
  line L6067 (22.643, -167.187) -> (22.1873, -166.821)
  line L6068 (131.257, -47.2539) -> (131.657, -47.6931)
  line L6069 (31.9179, -151.861) -> (31.3734, -151.624)
  line L6070 (139.816, -50.2345) -> (140.395, -50.0999)
  line L6071 (27.8893, -150.997) -> (27.2963, -151.029)
  line L6072 (134.985, -151.546) -> (134.434, -151.769)
  line L6073 (23.5183, -167.658) -> (24.0392, -167.943)
  line L6074 (44.3203, -152.967) -> (44.7829, -152.61)
  line L6075 (35.9457, -155.48) -> (36.2178, -155.997)
  line L6076 (132.085, -166.605) -> (132.539, -166.987)
  line L6077 (133.018, -167.339) -> (133.518, -167.658)
  line L6078 (36.3321, -156.48) -> (36.084, -155.94)
  line L6079 (136.123, -151.211) -> (135.548, -151.359)
  line L6080 (25.1318, -168.407) -> (25.6987, -168.583)
  line L6081 (145.879, -164.346) -> (146.153, -163.819)
  line L6082 (146.389, -45.0297) -> (146.14, -45.5586)
  line L6083 (43.4688, -153.766) -> (43.8816, -153.353)
  line L6084 (136.276, -168.722) -> (136.861, -168.822)
  line L6085 (133.518, -49.1579) -> (134.039, -49.4431)
  line L6086 (133.9, -152.029) -> (133.385, -152.323)
  line L6087 (139.258, -50.4226) -> (138.677, -50.4801)
  line L6088 (129.061, -42.2388) -> (129.029, -41.6553)
  line L6089 (34.42, -166.405) -> (33.9903, -166.801)
  line L6090 (145.133, -154.437) -> (144.753, -153.981)
  line L6091 (20.3113, -164.598) -> (20.0276, -164.087)
  line L6092 (21.8816, -153.353) -> (22.3203, -152.967)
  line L6093 (145.229, -165.339) -> (145.57, -164.853)
  line L6094 (36.7582, -162.147) -> (36.8847, -161.567)
  line L6095 (19.6834, -156.829) -> (19.495, -157.392)
  line L6096 (144.938, -35.5485) -> (145.304, -36.0036)
  line L6097 (129.131, -42.8189) -> (129.061, -42.2388)
  line L6098 (140.963, -50.0273) -> (140.404, -50.1957)
  line L6099 (36.8551, -158.18) -> (36.7185, -157.602)
  line L6100 (30.5713, -151.251) -> (31.1275, -151.43)
  line L6101 (138.483, -151.004) -> (137.889, -150.997)
  line L6102 (144.022, -48.1465) -> (144.453, -47.7378)
  line L6103 (143.441, -152.779) -> (142.954, -152.44)
  line L6104 (43.9695, -58.6007) -> (43.5489, -59.0199)
  line L6105 (19.1245, -159.731) -> (19.1297, -160.325)
  line L6106 (36.4559, -156.531) -> (36.6591, -157.078)
  line L6107 (146.922, -43.3625) -> (146.781, -43.9293)
  line L6108 (143.084, -167.374) -> (143.565, -167.026)
  line L6109 (44.7829, -152.61) -> (45.2676, -152.284)
  line L6110 (31.1275, -151.43) -> (31.671, -151.644)
  line L6111 (19.5618, -163.016) -> (19.3817, -162.46)
  line L6112 (140.395, -168.6) -> (140.963, -168.427)
  line L6113 (146.972, -160.979) -> (147.021, -160.387)
  line L6114 (31.5109, -168.323) -> (30.9634, -168.527)
  line L6115 (42.7955, -59.9371) -> (42.466, -60.4311)
  line L6116 (37.1268, -159.95) -> (37.1251, -160.124)
  line L6117 (136.861, -50.3221) -> (137.452, -50.3832)
  line L6118 (134.434, -151.769) -> (133.9, -152.029)
  line L6119 (19.7774, -163.559) -> (19.5618, -163.016)
  line L6120 (143.673, -34.338) -> (144.121, -34.714)
  line L6121 (129.909, -156.279) -> (129.683, -156.829)
  line L6122 (41.6223, -156.722) -> (41.8482, -156.183)
  line L6123 (36.2178, -155.997) -> (36.4559, -156.531)
  line L6124 (32.7108, -152.176) -> (33.2028, -152.492)
  line L6125 (143.084, -48.874) -> (143.565, -48.5258)
  line L6126 (144.543, -35.118) -> (144.938, -35.5485)
  line L6127 (142.044, -49.5841) -> (141.511, -49.8231)
  line L6128 (135.949, -32.6538) -> (136.521, -32.5348)
  line L6129 (36.9224, -161.862) -> (36.7806, -162.429)
  line L6130 (34.8557, -165.801) -> (35.2286, -165.339)
  line L6131 (19.2769, -157.837) -> (19.4315, -157.274)
  line L6132 (146.153, -163.819) -> (146.391, -163.276)
  line L6133 (28.6766, -168.98) -> (28.0926, -169)
  line L6134 (135.132, -49.9069) -> (135.699, -50.0835)
  line L6135 (36.5439, -157.035) -> (36.3321, -156.48)
  line L6136 (33.9903, -166.801) -> (33.5358, -167.168)
  line L6137 (147.032, -41.45) -> (147.012, -40.8565)
  line L6138 (139.816, -168.734) -> (140.395, -168.6)
  line L6139 (33.4411, -152.779) -> (32.954, -152.44)
  line L6140 (19.0612, -160.739) -> (19.0291, -160.155)
  line L6141 (130.311, -46.0975) -> (130.028, -45.5867)
  line L6142 (36.3914, -163.276) -> (36.5935, -162.717)
  line L6143 (21.3513, -166.006) -> (20.9746, -165.559)
  line L6144 (32.954, -152.44) -> (32.4456, -152.133)
  line L6145 (139.23, -50.3304) -> (139.816, -50.2345)
  line L6146 (144.121, -34.714) -> (144.543, -35.118)
  line L6147 (36.9531, -158.766) -> (36.8551, -158.18)
  line L6148 (22.417, -153.01) -> (21.9695, -153.401)
  line L6149 (132.085, -48.1049) -> (132.539, -48.4873)
  line L6150 (19.6222, -156.722) -> (19.8482, -156.183)
  line L6151 (144.342, -153.552) -> (143.904, -153.151)
  line L6152 (133.268, -33.7835) -> (133.772, -33.4892)
  line L6153 (138.85, -32.4331) -> (139.43, -32.5018)
  line L6154 (146.084, -155.94) -> (145.801, -155.418)
  line L6155 (146.885, -161.567) -> (146.972, -160.979)
  line L6156 (137.509, -50.4821) -> (136.927, -50.4266)
  line L6157 (30.3945, -168.6) -> (30.9627, -168.427)
  line L6158 (19.232, -158.549) -> (19.1587, -159.138)
  line L6159 (19.7392, -163.217) -> (19.9741, -163.763)
  line L6160 (146.758, -162.147) -> (146.885, -161.567)
  line L6161 (131.084, -35.7057) -> (131.469, -35.2664)
  line L6162 (30.9634, -168.527) -> (30.4039, -168.696)
  line L6163 (129.848, -37.6827) -> (130.108, -37.1595)
  line L6164 (44.417, -58.2104) -> (43.9695, -58.6007)
  line L6165 (130.795, -154.737) -> (130.466, -155.231)
  line L6166 (135.78, -50.2038) -> (135.22, -50.0373)
  line L6167 (41.9088, -61.4791) -> (41.6834, -62.0285)
  line L6168 (41.2769, -157.837) -> (41.4315, -157.274)
  line L6169 (43.5489, -59.0199) -> (43.157, -59.466)
  line L6170 (42.1085, -155.66) -> (42.402, -155.154)
  line L6171 (25.7803, -168.704) -> (25.2202, -168.537)
  line L6172 (19.495, -157.392) -> (19.3443, -157.966)
  line L6173 (129.432, -38.7738) -> (129.622, -38.2215)
  line L6174 (138.046, -168.905) -> (138.639, -168.887)
  line L6175 (135.22, -50.0373) -> (134.672, -49.8351)
  line L6176 (45.3845, -57.5228) -> (44.8893, -57.8505)
  line L6177 (21.157, -154.266) -> (20.7955, -154.737)
  line L6178 (21.6569, -166.193) -> (22.0847, -166.605)
  line L6179 (130.108, -37.1595) -> (130.402, -36.6542)
  line L6180 (36.3887, -163.53) -> (36.1404, -164.059)
  line L6181 (139.835, -50.3276) -> (139.258, -50.4226)
  line L6182 (30.4039, -168.696) -> (29.8346, -168.828)
  line L6183 (25.2202, -168.537) -> (24.672, -168.335)
  line L6184 (36.9725, -160.979) -> (37.0211, -160.387)
  line L6185 (23.7724, -151.989) -> (24.2951, -151.728)
  line L6186 (44.8893, -57.8505) -> (44.417, -58.2104)
  line L6187 (143.565, -167.026) -> (144.022, -166.647)
  line L6188 (19.3803, -162.086) -> (19.541, -162.658)
  line L6189 (19.8482, -156.183) -> (20.1085, -155.66)
  line L6190 (129.622, -38.2215) -> (129.848, -37.6827)
  line L6191 (20.0276, -164.087) -> (19.7774, -163.559)
  line L6192 (130.888, -46.7892) -> (131.257, -47.2539)
  line L6193 (34.1207, -153.214) -> (34.5428, -153.618)
  line L6194 (32.0441, -168.084) -> (31.5109, -168.323)
  line L6195 (130.975, -47.059) -> (130.627, -46.589)
  line L6196 (25.3856, -151.309) -> (25.9488, -151.154)
  line L6197 (34.453, -166.238) -> (34.8557, -165.801)
  line L6198 (19.1587, -159.138) -> (19.1245, -159.731)
  line L6199 (24.8336, -151.501) -> (25.3856, -151.309)
  line L6200 (133.018, -48.8389) -> (133.518, -49.1579)
  line L6201 (47.3856, -151.309) -> (47.9488, -151.154)
  line L6202 (19.0332, -159.731) -> (19.0347, -159.571)
  line L6203 (146.594, -162.717) -> (146.758, -162.147)
  line L6204 (34.5428, -153.618) -> (34.9379, -154.049)
  line L6205 (24.138, -168.098) -> (23.6204, -167.827)
  line L6206 (146.953, -40.2656) -> (146.855, -39.68)
  line L6207 (41.495, -62.5917) -> (41.3443, -63.166)
  line L6208 (35.5441, -165.063) -> (35.1986, -165.534)
  line L6209 (130.402, -36.6542) -> (130.727, -36.169)
  line L6210 (21.9695, -153.401) -> (21.5489, -153.82)
  line L6211 (33.5654, -167.026) -> (34.0223, -166.647)
  line L6212 (35.8785, -164.346) -> (36.1527, -163.819)
  line L6213 (129.562, -44.5156) -> (129.382, -43.9597)
  line L6214 (41.8482, -156.183) -> (42.1085, -155.66)
  line L6215 (26.1233, -151.211) -> (25.5484, -151.359)
  line L6216 (129.124, -159.731) -> (129.13, -160.325)
  line L6217 (145.199, -47.0342) -> (144.823, -47.4821)
  line L6218 (131.657, -47.6931) -> (132.085, -48.1049)
  line L6219 (146.719, -157.602) -> (146.544, -157.035)
  line L6220 (146.602, -44.4858) -> (146.389, -45.0297)
  line L6221 (145.57, -164.853) -> (145.879, -164.346)
  line L6222 (27.682, -150.909) -> (28.2663, -150.902)
  line L6223 (27.5085, -168.982) -> (26.9269, -168.927)
  line L6224 (143.99, -48.3008) -> (143.536, -48.6681)
  line L6225 (29.6626, -151.137) -> (29.075, -151.051)
  line L6226 (145.544, -46.563) -> (145.199, -47.0342)
  line L6227 (146.153, -45.3193) -> (146.391, -44.7756)
  line L6228 (24.5778, -168.193) -> (25.1318, -168.407)
  line L6229 (34.8234, -165.982) -> (34.42, -166.405)
  line L6230 (26.9269, -168.927) -> (26.35, -168.834)
  line L6231 (129.13, -160.325) -> (129.174, -160.917)
  line L6232 (26.2761, -168.722) -> (26.8615, -168.822)
  line L6233 (145.946, -36.9798) -> (146.218, -37.4969)
  line L6234 (22.7829, -152.61) -> (23.2676, -152.284)
  line L6235 (37.1251, -160.124) -> (37.0951, -160.707)
  line L6236 (26.8615, -168.822) -> (27.4521, -168.883)
  line L6237 (129.541, -44.1577) -> (129.739, -44.7175)
  line L6238 (24.9847, -151.546) -> (24.4345, -151.769)
  line L6239 (146.957, -39.7077) -> (147.051, -40.2844)
  line L6240 (130.245, -45.7915) -> (130.55, -46.301)
  line L6241 (41.6834, -62.0285) -> (41.495, -62.5917)
  line L6242 (147.127, -41.45) -> (147.125, -41.6237)
  line L6243 (22.539, -166.987) -> (23.0175, -167.339)
  line L6244 (146.332, -37.9798) -> (146.084, -37.4403)
  line L6245 (36.1404, -164.059) -> (35.8585, -164.57)
  line L6246 (25.5484, -151.359) -> (24.9847, -151.546)
  line L6247 (131.157, -154.266) -> (130.795, -154.737)
  line L6248 (27.4521, -168.883) -> (28.0455, -168.905)
  line L6249 (131.97, -153.401) -> (131.549, -153.82)
  line L6250 (134.039, -167.943) -> (134.578, -168.193)
  line L6251 (139.23, -168.83) -> (139.816, -168.734)
  line L6252 (36.9575, -158.208) -> (37.0514, -158.784)
  line L6253 (45.7724, -151.989) -> (46.2951, -151.728)
  line L6254 (132.783, -34.1099) -> (133.268, -33.7835)
  line L6255 (137.889, -150.997) -> (137.296, -151.029)
  line L6256 (36.5935, -162.717) -> (36.7582, -162.147)
  line L6257 (147.095, -42.2073) -> (147.027, -42.7877)
  line L6258 (129.382, -43.9597) -> (129.238, -43.3934)
  line L6259 (36.8266, -157.638) -> (36.9575, -158.208)
  line L6260 (29.8346, -168.828) -> (29.2581, -168.923)
  line L6261 (145.304, -36.0036) -> (145.641, -36.4813)
  line L6262 (140.404, -50.1957) -> (139.835, -50.3276)
  line L6263 (37.1079, -159.366) -> (37.1268, -159.95)
  line L6264 (20.6274, -165.089) -> (20.3113, -164.598)
  line L6265 (134.295, -33.228) -> (134.834, -33.0011)
  line L6266 (140.571, -32.7506) -> (141.128, -32.9297)
  line L6267 (43.8816, -153.353) -> (44.3203, -152.967)
  line L6268 (140.963, -168.427) -> (141.518, -168.217)
  line L6269 (36.1527, -163.819) -> (36.3914, -163.276)
  line L6270 (20.7274, -154.669) -> (21.0836, -154.206)
  line L6271 (144.753, -153.981) -> (144.342, -153.552)
  line L6272 (138.046, -50.4049) -> (138.639, -50.3873)
  line L6273 (19.0291, -160.155) -> (19.0332, -159.731)
  line L6274 (20.8876, -165.289) -> (21.2572, -165.754)
  line L6275 (134.578, -49.6931) -> (135.132, -49.9069)
  line L6276 (29.8162, -168.734) -> (30.3945, -168.6)
  line L6277 (137.099, -32.4529) -> (137.682, -32.4086)
  line L6278 (37.0514, -158.784) -> (37.1079, -159.366)
  line L6279 (34.3423, -153.552) -> (33.9045, -153.151)
  line L6280 (134.138, -49.5979) -> (133.62, -49.3267)
  line L6281 (24.672, -168.335) -> (24.138, -168.098)
  line L6282 (134.672, -49.8351) -> (134.138, -49.5979)
  line L6283 (46.2951, -151.728) -> (46.8336, -151.501)
  line L6284 (134.578, -168.193) -> (135.132, -168.407)
  line L6285 (141.511, -49.8231) -> (140.963, -50.0273)
  line L6286 (146.827, -39.1382) -> (146.957, -39.7077)
  line L6287 (37.0211, -160.387) -> (37.0318, -159.95)
  line L6288 (146.391, -163.276) -> (146.594, -162.717)
  line L6289 (130.17, -155.746) -> (129.909, -156.279)
  line L6290 (146.781, -43.9293) -> (146.602, -44.4858)
  line L6291 (28.8498, -150.933) -> (29.4301, -151.002)
  line L6292 (129.739, -44.7175) -> (129.974, -45.2629)
  line L6293 (129.159, -159.138) -> (129.124, -159.731)
  line L6294 (45.2676, -152.284) -> (45.7724, -151.989)
  line L6295 (141.671, -33.1443) -> (142.199, -33.3936)
  line L6296 (36.7185, -157.602) -> (36.5439, -157.035)
  line L6297 (33.2028, -152.492) -> (33.6734, -152.838)
  line L6298 (146.391, -44.7756) -> (146.594, -44.2172)
  line L6299 (139.663, -151.137) -> (139.075, -151.051)
  line L6300 (24.4345, -151.769) -> (23.9003, -152.029)
  line L6301 (35.2286, -165.339) -> (35.57, -164.853)
  line L6302 (145.879, -45.846) -> (146.153, -45.3193)
  line L6303 (46.8336, -151.501) -> (47.3856, -151.309)
  line L6304 (142.059, -49.4711) -> (142.581, -49.1896)
  line L6305 (130.627, -46.589) -> (130.311, -46.0975)
  line L6306 (35.4833, -154.917) -> (35.1334, -154.437)
  line L6307 (35.3045, -154.504) -> (35.6409, -154.981)
  line L6308 (137.452, -168.883) -> (138.046, -168.905)
  line L6309 (37.0951, -160.707) -> (37.0274, -161.288)
  line L6310 (142.446, -152.133) -> (141.918, -151.861)
  line L6311 (19.2379, -161.893) -> (19.1309, -161.319)
  line L6312 (28.0455, -168.905) -> (28.6391, -168.887)